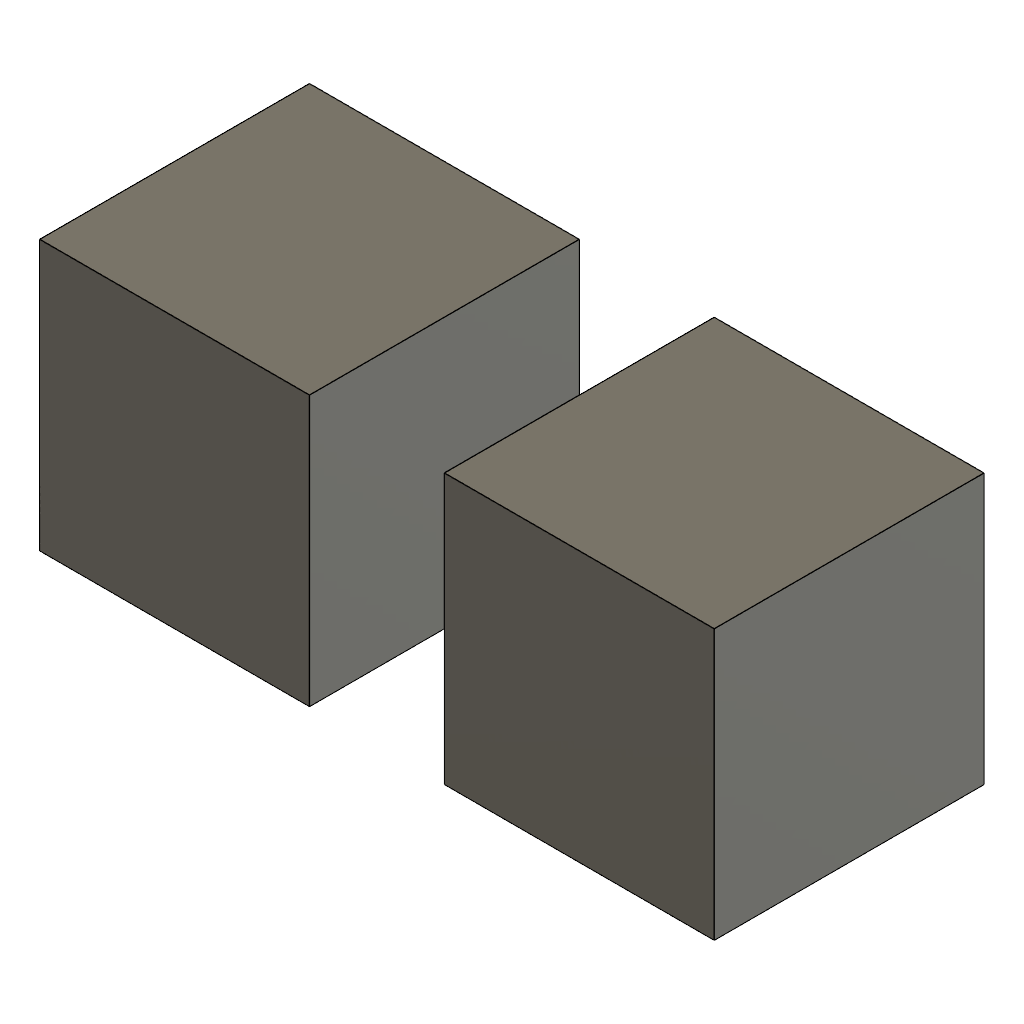
extrude_to_face (Autodesk Fusion 360 design; units mm, degrees)
part number: 2026-11-10-15-06-40-715
Autodesk Fusion 360 part; units mm, degrees
sketch "Sketch1" plane through (0, 0, 0) normal (0, 0, 1) x (1, 0, 0)
  line L0 (0, 0) -> (10, 0)
  line L1 (10, 0) -> (10, 10)
  line L2 (10, 10) -> (0, 10)
  line L3 (0, 10) -> (0, 0)
extrude "Extrude1" add sketch "Sketch1" along normal blind 10 makes body 1
sketch "Sketch2" plane through (0, 0, 0) normal (0, 0, 1) x (1, 0, 0)
  line L0 (15, 0) -> (25, 0)
  line L1 (25, 0) -> (25, 10)
  line L2 (25, 10) -> (15, 10)
  line L3 (15, 10) -> (15, 0)
extrude "Extrude2" add sketch "Sketch2" along normal up to surface (10 mm away) separate body makes body 2
